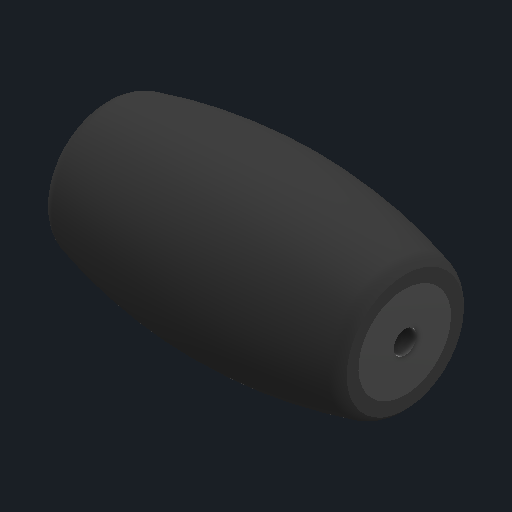
# Autodesk Inventor part: Rolete
Saved by Autodesk Inventor 2026.1 (Build 301233000, 233)
## iProperties
Created: 2025-01-03
Part Number: Rolete
Material: ABS plástico
Document SubType Name: Modeling
Designer: Cliente
Density: 0.916199 g/cm^3
Appearance: Borracha - Preta
Mass: 8.272 g
Surface Area: 66.403 cm^2
Volume: 9.02861 cm^3
Author: Cliente
Autodesk Inventor part; units mm, degrees
ref_plane "YZ Plane" through (0, 0, 0) normal (1, 0, 0) x (0, 1, 0)
ref_plane "XZ Plane" through (0, 0, 0) normal (0, 1, 0) x (-1, 0, 0)
ref_plane "XY Plane" through (0, 0, 0) normal (0, 0, 1) x (1, 0, 0)
sketch "Esboço1" plane through (0, 0, 0) normal (0, 0, 1) x (1, 0, 0)
  circle A0 centre (0, 0) radius 59.5
  line L0 (0, 0) -> (0, 50)
  line L1 (-17.5, 50) -> (17.5, 50)
  line L2 (-17.5, 50) -> (-17.5, 56.8683)
  line L3 (17.5, 50) -> (17.5, 56.8683)
  line L4 (-17.5, 51.35) -> (17.5, 51.35)
  dimension "d0" = 119
  dimension "d1" = 50
  dimension "d2" = 35
  dimension "d3" = 1.35
  constraints: 10 end point, 2 parallel, 2 point on circle, 2 point on line, 2 vertical, 1 centre point, 1 coincident, 1 horizontal, 1 midpoint
  measures "d0" diameter of A0
  measures "d1" distance of L0.end L0.start
  measures "d2" distance of L1.start L1.end
  measures "d3" distance between parallel lines of L1 L4
revolve "Revolução1" add sketch "Esboço1" angle 360 about axis through (-17.5, 50, 0) along (1, 0, 0) contours L3 L4 L2 A0
fillet "Arredondamento2" radius 2 2 edges at (17.5, 43.1317, 0) (-17.5, 43.1317, 0)
sketch "Esboço2" plane through (0, 0, 0) normal (0, 0, 1) x (1, 0, 0)
  line L0 (16.0391, 42.7026) -> (16.0391, 57.2974) projected
  line L1 (-16.0391, 57.2974) -> (-16.0391, 42.7026) projected
  line L2 (-17.5, 44.6285) -> (-17.5, 55.3715) projected
  line L3 (-16.0391, 57.2974) -> (-16.0391, 42.7026) projected
  arc A0 (16.0391, 57.2974) -> (-16.0391, 57.2974) centre (0, 0) ccw projected
  arc A1 (-16.0391, 57.2974) -> (-17.5, 55.3715) centre (-15.5, 55.3715) ccw projected
  arc A2 (17.5, 55.3715) -> (16.0391, 57.2974) centre (15.5, 55.3715) ccw projected
  line L4 (17.5, 55.3715) -> (17.5, 44.6285) projected
  arc A3 (16.1739, 57.7789) -> (-16.1739, 57.7789) centre (0, 0) ccw
  arc A4 (-16.1739, 57.7789) -> (-18, 55.3715) centre (-15.5, 55.3715) ccw
  arc A5 (18, 55.3715) -> (16.1739, 57.7789) centre (15.5, 55.3715) ccw
  line L5 (18, 55.3715) -> (18, 44.6285)
  line L6 (-17.5, 55.3715) -> (-17.5, 57.6609)
  line L7 (17.5, 55.3715) -> (17.5, 57.9541)
  line L8 (17.5, 50) -> (-17.5, 50)
  point P0 (17.5, 56.8715)
  point P1 (-17.5, 56.8715)
  dimension "d7" = 0.5
  dimension "d8" = 0.5
  dimension "d9" = 0.5
  constraints: 8 end point, 6 point on circle, 3 centre point, 2 midpoint, 2 vertical, 1 other
  measures "d7" radial gap between concentric circles of A0 A3
  measures "d8" radial gap between concentric circles of A1 A4
  measures "d9" radial gap between concentric circles of A2 A5
revolve "Revolução2" add sketch "Esboço2" angle 360 about axis through (17.5, 50, 0) along (-1, 0, 0) separate body contours A0 A1 L6 A4 A3 A5 L7 A2
